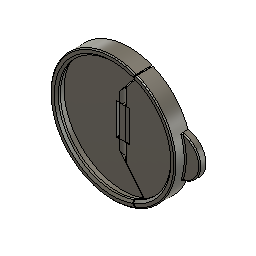
Dosendeckel (Autodesk Fusion 360 design; units mm, degrees)
Autodesk Fusion 360 part; units mm, degrees
sketch "Skizze1" plane through (0, 0, 0) normal (0, 0, 1) x (1, 0, 0)
  circle A0 centre (0, 0) radius 27.2
  circle A1 centre (0, 0) radius 30.2
  line L0 (0, 27.2) -> (0, -27.2) construction
  line L1 (3, -7.5) -> (-3, -7.5)
  line L2 (-3, -7.5) -> (-3, 7.5)
  line L3 (-3, 7.5) -> (3, 7.5)
  line L4 (3, 7.5) -> (3, -7.5)
  line L5 (3, -7.5) -> (-3, 7.5) construction
  line L6 (-3, -7.5) -> (3, 7.5) construction
  line L7 (3.1, -7.6) -> (-3.1, -7.6)
  line L8 (-3.1, -7.6) -> (-3.1, 7.6)
  line L9 (-3.1, 7.6) -> (3.1, 7.6)
  line L10 (3.1, 7.6) -> (3.1, -7.6)
  line L11 (0.25, -14) -> (-0.25, -14)
  line L12 (-0.25, -14) -> (-0.25, 14)
  line L13 (-0.25, 14) -> (0.25, 14)
  line L14 (0.25, 14) -> (0.25, -14)
  line L15 (0.25, -14) -> (-0.25, 14) construction
  line L16 (-0.25, -14) -> (0.25, 14) construction
  line L17 (0, 14) -> (13.1557, 30.246) construction
  line L18 (0, 14) -> (20.9047, 14) construction
  line L19 (0.1943, 13.8427) -> (13.35, 30.0887) construction
  line L20 (-0.1943, 14.1573) -> (12.9615, 30.4033) construction
  line L21 (-30.2, 0) -> (30.2, 0) construction
  line L22 (-0.25, 14) -> (11.0887, 28.0906)
  line L23 (0.25, 14) -> (11.5732, 27.8945)
  line L24 (0.25, -14) -> (11.5732, -27.8945)
  line L25 (-0.25, -14) -> (11.0887, -28.0906)
  dimension "d1" = 54.4
  dimension "d2" = 3
  dimension "d3" = 6
  dimension "d4" = 15
  dimension "d5" = -0.1
  dimension "d6" = 0.5
  dimension "d7" = 28
  dimension "d8" = 51
  dimension "d9" = 0.25
  dimension "d10" = -0.25
  constraint coincident A0.centre A1.centre
  constraint coincident A0 L0.start
  constraint coincident A0 L0.end
  constraint vertical L0
  constraint horizontal L1
  constraint perpendicular L1 L2
  constraint parallel L1 L3
  constraint parallel L2 L4
  constraint coincident L5 A0.centre
  constraint coincident L6 A0.centre
  constraint horizontal L11
  constraint perpendicular L11 L12
  constraint parallel L11 L13
  constraint parallel L12 L14
  constraint coincident L15 A0.centre
  constraint coincident L16 A0.centre
  constraint horizontal L18
  constraint midpoint L13 L17.start
  constraint coincident A1 L21.start
  constraint coincident A1 L21.end
  constraint horizontal L21
  constraint coincident L20 L22.end
  constraint coincident A1 L22.end
  constraint coincident A1 L23.end
  constraint coincident L19 L23.end
  constraint symmetric L12.end L21 L11.end
  constraint symmetric L13.end L21 L11.start
  constraint symmetric L21 L22.end L25.end
  constraint symmetric L21 L23.end L24.end
  measures "d1" diameter of A0
  measures "d3" distance of L2.end L3.end
  measures "d4" distance of L1.end L2.end
  measures "d6" distance of L12.end L13.end
  measures "d7" distance of L11.end L12.end
  measures "d8" angle of L17 L18
extrude "Extrusion1" add sketch "Skizze1" against normal blind 3 contours A0 L7 L9 L10 L14 L23 L24 | A0 A1 L23 L24 | A0 L7 L8 L9 L12 L22 L25 | A0 A1 L22 L25 | L1 L3 L12 L14 | L1 L3 L4 L14 | L1 L2 L3 L12 makes body 1 at (12.1333, 0, 0) makes body 2 at (-12.1333, 0, 0) makes body 3 at (-1, 2.5, 0)
extrude "Extrusion2" add sketch "Skizze1" along normal blind 5 contours A0 A1 L23 L24 | A0 A1 L22 L25 bodies 1 2
sketch "Skizze2" plane through (0, 0, 0) normal (1, 0, 0) x (0, 0, -1)
  line L0 (0, 27.2) -> (0, -27.2) construction
  line L1 (-5, 30.2) -> (-5, -30.2) construction
  line L2 (3, -30.2) -> (3, 30.2) construction
  line L3 (-5, -27.2) -> (-5, 27.2) construction
  line L4 (-5, 27.4107) -> (-3, 27.4107) construction
  line L5 (-3, 27.4107) -> (-3, 28.4107) construction
  line L6 (-3, 28.4107) -> (-5, 28.4107) construction
  line L7 (-5, 28.4107) -> (-5, 27.4107) construction
  line L8 (0, 27.2) -> (-3, 27.2)
  line L9 (-3, 27.2) -> (-3, 28.4107)
  line L10 (-3, 28.4107) -> (0, 28.4107)
  line L11 (0, 28.4107) -> (0, 27.2)
  dimension "d15" = 2
  dimension "d16" = 1
  constraint horizontal L4
  constraint vertical L5
  constraint horizontal L6
  constraint vertical L7
  constraint coincident L1 L4.start
  constraint horizontal L8
  constraint vertical L9
  constraint horizontal L10
  constraint vertical L11
  constraint coincident L0.start L8.start
  measures "d15" distance of L4.start L4.end
  measures "d16" distance of L4.start L6.end
revolve "Drehen1" cut sketch "Skizze2" angle 360 about axis through (0, 0, 1.75) along (0, 0, 1) bodies 1 2
chamfer "Fase1" distance 1 angle 45 2 edges at (27.2, 0, 5) (-27.2, 0, 5) on bodies 1 2
fillet "Abrundung1" radius 1.5 4 edges at (-3, 0, 0) (-3, 0, -3) (3, 0, 0) (3, 0, -3) on bodies 3
sketch "Skizze3" plane through (0, 0, 0) normal (0, 1, 0) x (1, 0, 0)
  arc A0 (1.5, 0) -> (1.5, 3) centre (1.5, 1.5) ccw construction
  arc A1 (-1.5, 3) -> (-1.5, 0) centre (-1.5, 1.5) ccw construction
  line L0 (1.5, 3) -> (-1.5, 3) construction
  line L1 (1.5, 0) -> (-1.5, 0) construction
  circle A2 centre (-1.5, 1.5) radius 0.5
  circle A3 centre (1.5, 1.5) radius 0.5
  dimension "d21" = 1
  dimension "d22" = 1
  constraint concentric A1 A2
  constraint concentric A0 A3
  measures "d21" diameter of A2
  measures "d22" diameter of A3
extrude "Extrusion3" add sketch "Skizze3" along normal mid plane 16.6 bodies 3
sketch "Skizze4" plane through (0, 0, 0) normal (0, 1, 0) x (1, 0, 0)
  circle A0 centre (-1.5, 1.5) radius 0.5 construction
  circle A1 centre (1.5, 1.5) radius 0.5 construction
  circle A2 centre (1.5, 1.5) radius 0.55
  circle A3 centre (-1.5, 1.5) radius 0.55
  dimension "d25" = 1.1
  dimension "d26" = 1.1
  constraint concentric A1 A2
  constraint concentric A0 A3
  measures "d25" diameter of A2
  measures "d26" diameter of A3
extrude "Extrusion4" cut sketch "Skizze4" along normal mid plane 17 bodies 1 2
fillet "Abrundung2" radius 0.5 4 edges at (-1.9662, 8.3, -1.3192) (1.0338, 8.3, -1.3192) (1.0338, -8.3, -1.6808) (-1.9662, -8.3, -1.6808) on bodies 3
fillet "Abrundung3" radius 1.5 8 edges at (0.25, -10.8, 0) (0.25, 10.8, 0) (0.25, -10.8, -3) (0.25, 10.8, -3) (-0.25, -10.8, 0) (-0.25, 10.8, 0) (-0.25, -10.8, -3) (-0.25, 10.8, -3) on bodies 1 2
sketch "Skizze5" plane through (0, 0, 0) normal (0, 0, 1) x (1, 0, 0)
  arc A0 (11.5732, -27.8945) -> (11.5732, 27.8945) centre (0, 0) ccw construction
  arc A1 (9.5853, -25.4551) -> (9.5853, 25.4551) centre (0, 0) ccw construction
  arc A2 (10.39, -26.4426) -> (10.39, 26.4426) centre (0, 0) ccw construction
  circle A3 centre (27.2, 0) radius 10
  dimension "d33" = 20
  constraint midpoint A1 A3.centre
  measures "d33" diameter of A3
extrude "Extrusion5" add sketch "Skizze5" against normal blind 3 bodies 1
fillet "Abrundung4" radius 0.5 2 edges at (30.2, 0, 5) (-30.2, 0, 5) on bodies 1 2
fillet "Abrundung5" radius 0.5 2 edges at (37.2, 0, 0) (30.2, 0, 0) on bodies 1
equation "d10 = -d9"
named bodies: "Klappe", "Deckel", "Schanier"
